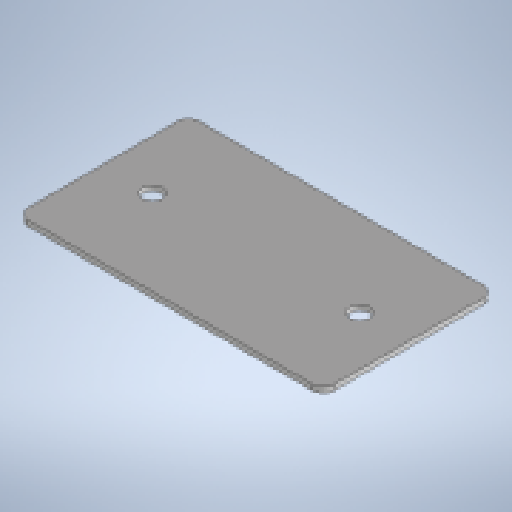
# Autodesk Inventor part: DMF-7xxx 2hole plate
Saved by Autodesk Inventor 2026.2 (Build 302298000, 298)
## iProperties
Created: 2026-06-04
Part Number: DMF-7xxx 2hole plate
Material: Generic
Description: DIE16(5)|\ 90°|corrY -___°|X_____|bom___
Document SubType Name: Sheet Metal
Designer: admin
Stock Number: DMF-4103
Mass: 1762.25 g
Surface Area: 2283.33 cm^2
Volume: 220.281 cm^3
Density: 1 g/cm^3
Sheet Metal Rule: Default
Sheet Metal Width: 0,000 mm
Sheet Metal Length: 0,000 mm
Sheet Metal Area: 0,000 mm^2
Appearance: Default
Author: admin
Autodesk Inventor part; units mm, degrees
ref_plane "YZ Plane" through (0, 0, 0) normal (1, 0, 0) x (0, 1, 0)
ref_plane "XZ Plane" through (0, 0, 0) normal (0, 1, 0) x (-1, 0, 0)
ref_plane "XY Plane" through (0, 0, 0) normal (0, 0, 1) x (1, 0, 0)
sketch "Sketch10" plane through (0, 0, 0) normal (0, 0, 1) x (1, 0, 0)
  line L0 (85, -47.5) -> (-85, -47.5)
  line L1 (-85, -47.5) -> (-85, 47.5)
  line L2 (-85, 47.5) -> (85, 47.5)
  line L3 (85, 47.5) -> (85, -47.5)
  line L4 (85, -47.5) -> (-85, 47.5) construction
  line L5 (-85, -47.5) -> (85, 47.5) construction
  point P0 (0, 0)
  dimension "d200" = 170
  dimension "d201" = 95
  measures "d200" distance of L0.start L0.end
  measures "d201" distance of L0.end L1.end
extrude "Plate8" add sketch "Sketch10" along normal blind 3
sketch "Sketch11" plane through (0, 0, 3) normal (0, 0, 1) x (1, 0, 0)
  circle A0 centre (57.5, 0) radius 5.5
  circle A1 centre (-57.5, 0) radius 5.5
  line L0 (57.5, 0) -> (-57.5, 0)
  point P0 (0, 0)
  point P1 (0, 0)
  dimension "d203" = 11
  dimension "d204" = 115
  constraints: 2 centre point, 2 end point, 1 coincident, 1 equal radius, 1 horizontal, 1 midpoint
  measures "d203" diameter of A0
  measures "d204" distance of L0.end L0.start
extrude "Cut2" cut sketch "Sketch11" against normal blind 3
fillet "Corner Round3" radius 6 4 edges at (-85, 47.5, 1.5) (-85, -47.5, 1.5) (85, 47.5, 1.5) (85, -47.5, 1.5)
body "Solid4"
